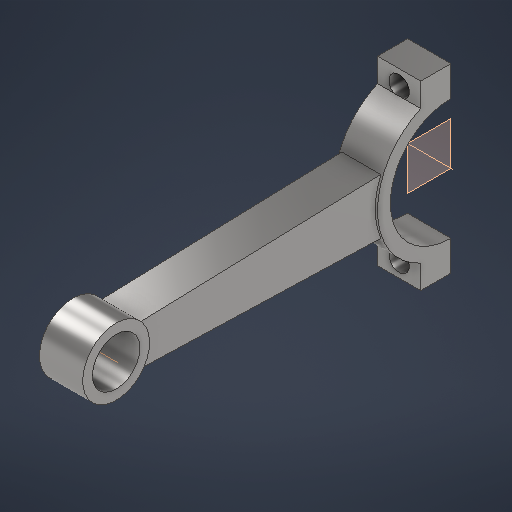
# Autodesk Inventor part: Con_Rod
Saved by Autodesk Inventor 2027.1 (Build 311270010, 270A)
## iProperties
Created: 2026-10-17
Part Number: Con_Rod
Material: Steel, Alloy
Document SubType Name: Modeling
Designer: kashyap
Density: 7.73 g/cm^3
Appearance: Semi-Polished
Mass: 502.841 g
Surface Area: 191.211 cm^2
Volume: 65.0506 cm^3
Material_Status: Assumed for this reconstruction
Author: kashyap
Autodesk Inventor part; units mm, degrees
derived "V6_Engine_Master.ipt"
ref_plane "Rod_SmallEnd_Plane" through (0, 0, 155) normal (0, 0, 1) x (1, 0, 0)
ref_plane "Rod_Mid_Plane" through (0, 0, 0) normal (1, 0, 0) x (0, 1, 0)
ref_plane "Rod_Split_Plane" through (0, 0, 0) normal (0, 0, 1) x (1, 0, 0)
sketch "SK_BigEnd" plane through (0, 0, 0) normal (1, 0, 0) x (0, 1, 0)
  circle A0 centre (0, 0) radius 34
  dimension "d22" = 68
  constraints: 1 centre point
  measures "d22" diameter of A0
extrude "BigEnd_Eye" add sketch "SK_BigEnd" along normal mid plane 20
sketch "SK_Bolt_Bosses" plane through (0, 0, 0) normal (1, 0, 0) x (0, 1, 0)
  line L0 (0, 16.8) -> (0, -2.8) construction
  line L1 (-58.8, 0) -> (58.8, 0) construction
  line L2 (-42, 0) -> (42, 0)
  line L3 (42, 0) -> (42, 14)
  line L4 (42, 14) -> (-42, 14)
  line L5 (-42, 14) -> (-42, 0)
  dimension "d25" = 42
  dimension "d26" = 42
  dimension "d27" = 14
  constraints: 8 end point, 2 parallel, 1 collinear, 1 horizontal, 1 perpendicular
  measures "d25" distance between parallel lines of L5 L0
  measures "d26" distance between parallel lines of L3 L0
  measures "d27" distance between parallel lines of L4 L1
extrude "Bolt_Bosses" add sketch "SK_Bolt_Bosses" along normal mid plane 20
sketch "SK_Beam" plane through (0, 0, 0) normal (1, 0, 0) x (0, 1, 0)
  line L0 (0, 181) -> (0, -1) construction
  line L1 (-18.2, 0) -> (18.2, 0) construction
  line L2 (-18.2, 155) -> (18.2, 155) construction
  line L3 (-13, 25) -> (13, 25)
  line L4 (13, 25) -> (9, 155)
  line L5 (9, 155) -> (-9, 155)
  line L6 (-9, 155) -> (-13, 25)
  dimension "d30" = 26
  dimension "d31" = 18
  dimension "d32" = 25
  constraints: 8 end point, 2 horizontal, 2 symmetric about line, 1 collinear
  measures "d30" distance of L3.start L3.end
  measures "d31" distance of L5.end L4.end
  measures "d32" distance between parallel lines of L3 L1
extrude "Beam" add sketch "SK_Beam" along normal mid plane 18
sketch "SK_SmallEnd" plane through (0, 0, 0) normal (1, 0, 0) x (0, 1, 0)
  circle A0 centre (0, 155) radius 15.5
  dimension "d35" = 31
  constraints: 1 centre point
  measures "d35" diameter of A0
extrude "SmallEnd_Eye" add sketch "SK_SmallEnd" along normal mid plane 20
sketch "SK_Split_Cut" plane through (0, 0, 0) normal (1, 0, 0) x (0, 1, 0)
  line L0 (-84, 0) -> (84, 0) construction
  line L1 (-60, 0) -> (60, 0)
  line L2 (60, 0) -> (60, -60)
  line L3 (60, -60) -> (-60, -60)
  line L4 (-60, -60) -> (-60, 0)
  constraints: 8 end point, 2 parallel, 1 horizontal, 1 perpendicular
extrude "Split_Cut" cut sketch "SK_Split_Cut" along normal mid plane 22
sketch "SK_BigEnd_Bore" plane through (0, 0, 0) normal (1, 0, 0) x (0, 1, 0)
  circle A0 centre (0, 0) radius 28.028
  dimension "d40" = 56.056
  constraints: 1 centre point
  measures "d40" diameter of A0
extrude "BigEnd_Bore" cut sketch "SK_BigEnd_Bore" along normal mid plane 22
sketch "SK_SmallEnd_Bore" plane through (0, 0, 0) normal (1, 0, 0) x (0, 1, 0)
  circle A0 centre (0, 155) radius 11.004
  dimension "d43" = 22.008
  constraints: 1 centre point
  measures "d43" diameter of A0
extrude "SmallEnd_Bore" cut sketch "SK_SmallEnd_Bore" along normal mid plane 22
sketch "SK_Bolt_Holes" plane through (0, 0, 0) normal (0, 0, 1) x (1, 0, 0)
  circle A0 centre (0, 35) radius 4.75
  circle A1 centre (0, -35) radius 4.75
  line L0 (-6.65, 0) -> (6.65, 0) construction
  line L1 (0, 55.65) -> (0, -55.65) construction
  point P0 (0, 0)
  dimension "d46" = 9.5
  dimension "d47" = 9.5
  dimension "d50" = 35
  dimension "d51" = 35
  constraints: 2 centre point, 2 point on line
  measures "d46" diameter of A0
  measures "d47" diameter of A1
  measures "d50" distance from line of L0 A0.centre
  measures "d51" distance from line of L0 A1.centre
extrude "Bolt_Holes" cut sketch "SK_Bolt_Holes" along normal blind 14
equation "\"d22\" = Rod_BigEnd_OD"
equation "\"d23\" = Rod_BigEnd_Width"
equation "\"d25\" = Rod_Boss_Half_Width"
equation "\"d26\" = Rod_Boss_Half_Width"
equation "\"d27\" = Rod_Boss_Height"
equation "\"d28\" = Rod_BigEnd_Width"
equation "\"d30\" = Rod_Beam_Width_Big"
equation "\"d31\" = Rod_Beam_Width_Small"
equation "\"d35\" = Rod_SmallEnd_OD"
equation "\"d36\" = Rod_SmallEnd_Width"
equation "\"d40\" = Rod_BigEnd_Bore"
equation "\"d43\" = Rod_SmallEnd_Bore"
equation "\"d46\" = Rod_Bolt_Hole_Dia"
equation "\"d47\" = Rod_Bolt_Hole_Dia"
equation "\"d50\" = Rod_Bolt_Y"
equation "\"d51\" = Rod_Bolt_Y"
equation "\"d48\" = Rod_Boss_Height"
equation "\"Rod_BigEnd_OD\" = 68"
equation "\"Rod_BigEnd_Width\" = 20"
equation "\"Rod_Boss_Half_Width\" = 42"
equation "\"Rod_Boss_Height\" = 14"
equation "\"Rod_Beam_Width_Big\" = 26"
equation "\"Rod_Beam_Width_Small\" = 18"
equation "\"Rod_SmallEnd_OD\" = 31"
equation "\"Rod_SmallEnd_Width\" = 20"
equation "\"Rod_BigEnd_Bore\" = 56.056"
equation "\"Rod_SmallEnd_Bore\" = 22.008"
equation "\"Rod_Bolt_Hole_Dia\" = 9.5"
equation "\"Rod_Bolt_Y\" = 35"
body "Solid1"
